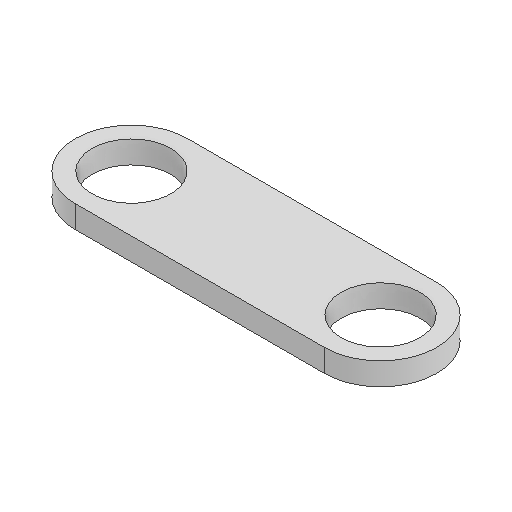
# Autodesk Inventor part: bar_dc
Saved by Autodesk Inventor 2026.1 (Build 301233020, 233B)
## iProperties
Created: 2025-11-26
Part Number: bar_dc
Material: Genérico
Document SubType Name: Modeling
Designer: matia
Density: 1 g/cm^3
Appearance: Valor por defecto
Author: matia
Autodesk Inventor part; units mm, degrees
ref_plane "YZ Plane" through (0, 0, 0) normal (1, 0, 0) x (0, 1, 0)
ref_plane "XZ Plane" through (0, 0, 0) normal (0, 1, 0) x (-1, 0, 0)
ref_plane "XY Plane" through (0, 0, 0) normal (0, 0, 1) x (1, 0, 0)
sketch "Sketch1" plane through (0, 0, 0) normal (0, 1, 0) x (-1, 0, 0)
  circle A0 centre (0, 0) radius 5
  circle A1 centre (-44.3, 0) radius 5
  line L0 (0, 0) -> (-44.3, 0) construction
  line L1 (0, 10) -> (-44.3, 10)
  line L2 (-44.3, -10) -> (0, -10)
  arc A2 (0, -10) -> (0, 10) centre (0, 0) ccw
  arc A3 (-44.3, 10) -> (-44.3, -10) centre (-44.3, 0) ccw
  circle A4 centre (0, 0) radius 7
  circle A5 centre (-44.3, 0) radius 7
  point P0 (-22.15, 0)
  dimension "d_hole" = 10
  dimension "l_c" = 44.3
  dimension "w_cd" = 20
  dimension "d4" = 14
  dimension "d6" = 14
  dimension "d7" = 10
  constraints: 8 end point, 6 centre point, 4 point on circle, 4 tangent, 3 coincident, 1 horizontal, 1 midpoint, 1 parallel
  measures "d_hole" diameter of A0
  measures "l_c" distance of L0.end point (0, 0)
  measures "w_cd" diameter of A3
  measures "d4" diameter of A4
  measures "d6" diameter of A5
  measures "d7" diameter of A1
extrude "Extrusion1" add sketch "Sketch1" along normal blind 4 contours A2 L2 A3 L1
equation "\"d7\" = d_hole"
body "Solid1"
